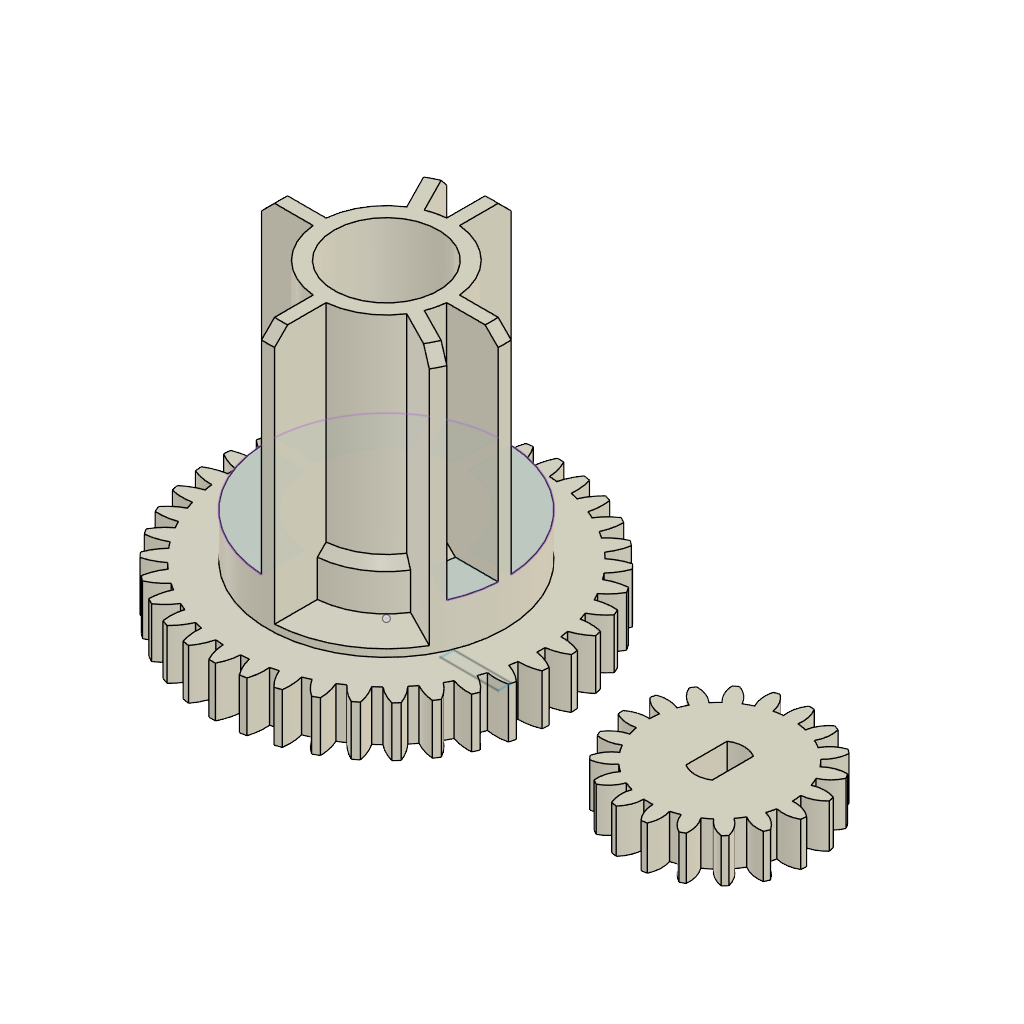
Roue_Store_D27 et pignon (Autodesk Fusion 360 design; units mm, degrees)
Autodesk Fusion 360 part; units mm, degrees
note: some values were not read from the file. Set by a fixed rule: which face or edge a step refers to.
sketch "Esquisse1" plane through (0, 0, 0) normal (0, 0, 1) x (1, 0, 0)
  circle A0 centre (0, 0) radius 17.75
  dimension "d1" = 35.5
  measures "d1" diameter of A0
extrude "Extrusion1" add sketch "Esquisse1" along normal blind 5.75 makes body 1
sketch "Esquisse2" plane through (0, 0, 0) normal (0, 0, 1) x (1, 0, 0)
  circle A0 centre (0, 0) radius 13.6
  dimension "d4" = 27.2
  measures "d4" diameter of A0
extrude "Extrusion2" add sketch "Esquisse2" along normal blind 5.05 from surface at 5.75 bodies 1
sketch "Esquisse3" plane through (0, 0, 0) normal (0, 0, 1) x (1, 0, 0)
  circle A0 centre (0, 0) radius 7.7
  dimension "d8" = 15.4
  measures "d8" diameter of A0
extrude "Extrusion3" add sketch "Esquisse3" along normal blind 24.8 from surface at 10.8 bodies 1
sketch "Esquisse4" plane through (0, 0, 0) normal (0, 0, 1) x (1, 0, 0)
  circle A0 centre (0, 0) radius 11
  dimension "d12" = 22
  measures "d12" diameter of A0
extrude "Extrusion4" cut sketch "Esquisse4" along normal blind 5.5 bodies 1
sketch "Esquisse5" plane through (0, 0, 0) normal (0, 0, 1) x (1, 0, 0)
  circle A0 centre (0, 0) radius 3
  dimension "d15" = 6
  measures "d15" diameter of A0
extrude "Extrusion5" cut sketch "Esquisse5" along normal through all bodies 1
sketch "Esquisse6" plane through (0, 0, 0) normal (0, 0, 1) x (1, 0, 0)
  circle A0 centre (0, 0) radius 6
  dimension "d17" = 12
  measures "d17" diameter of A0
extrude "Extrusion6" cut sketch "Esquisse6" against normal blind 20 from surface at 35.6 bodies 1
chamfer "Chanfrein1" distance 1 angle 45 1 edges at (-7.1789, 2.7844, 10.8) tangent chain off on bodies 1
chamfer "Chanfrein2" distance 1.4 angle 45 1 edges at (-5.594, 2.1697, 15.6) tangent chain off on bodies 1
sketch "Esquisse7" plane through (0, 0, 0) normal (0, 0, 1) x (1, 0, 0)
  arc A0 (0.3802, 19.9957) -> (-0.3768, 19.9957) centre (0.0017, -0.0007) ccw
  arc A1 (1.0258, 17.4199) -> (-1.0222, 17.4199) centre (0.0018, 0) ccw
  arc A2 (1.0258, 17.4199) -> (0.3802, 19.9957) centre (-4.7875, 17.3315) ccw
  arc A3 (-0.3768, 19.9957) -> (-1.0222, 17.4199) centre (4.7912, 17.3321) ccw
  dimension "d23" = 40
  dimension "d24" = 34.9
  dimension "d25" = 5.814
  dimension "d26" = 0.757
  dimension "d27" = 2.048
  constraint coincident A0.start A2.end
  constraint coincident A1.start A2.start
  constraint coincident A0.end A3.start
  constraint coincident A1.end A3.end
  constraint horizontal A0.start A0.end
  constraint horizontal A1.start A1.end
  constraint equal A2 A3
  measures "d23" diameter of A0
  measures "d24" diameter of A1
  measures "d25" radius of A2
  measures "d26" horizontal distance of A0.start A0.end
  measures "d27" horizontal distance of A1.start A1.end
extrude "Extrusion7" add sketch "Esquisse7" along normal blind 5.75 bodies 1
pattern_circular "Réseau C1" count 38 over 360 about axis through (0, 0, 1.75) along (0, 0, 1) of "Extrusion7"
sketch "Esquisse8" plane through (0, 0, 0) normal (0, 0, 1) x (1, 0, 0)
  arc A0 (13.5793, -0.75) -> (13.5793, 0.75) centre (0, 0) ccw
  arc A1 (6.9597, -0.75) -> (6.9597, 0.75) centre (0, 0) ccw
  line L0 (13.5793, 0.75) -> (6.9597, 0.75)
  line L1 (13.5793, -0.75) -> (6.9597, -0.75)
  dimension "d32" = 27.2
  dimension "d33" = 14
  dimension "d34" = 1.5
  dimension "d35" = 0.75
  constraint horizontal L0
  constraint horizontal L1
  measures "d32" diameter of A0
  measures "d33" diameter of A1
  measures "d34" vertical distance of A0.start A0.end
  measures "d35" vertical distance of A0.centre A0.end
extrude "Extrusion8" add sketch "Esquisse8" along normal blind 24.8 from surface at 10.8 bodies 1
pattern_circular "Réseau C2" count 4 over 360 about axis through (0, 0, 1.75) along (0, 0, 1) of "Extrusion8"
pattern_circular "Réseau C3" count 2 over 117 about axis through (0, 0, 1.75) along (0, 0, 1) of "Extrusion8"
pattern_circular "Réseau C4" count 2 over 333 about axis through (0, 0, 1.75) along (0, 0, 1) of "Extrusion8"
extrude "Extrusion9" cut 1 faces at (1.385, -11.8617, 10.8) along direction (0, 0, -1) blind 4.2 on bodies 1 bodies 1
chamfer "Chanfrein3" distance 1.5 angle 45 6 edges at (12.1177, -6.1743, 35.6) (13.6, 0, 35.6) (0, 13.6, 35.6) (-6.1743, 12.1177, 35.6) (-13.6, 0, 35.6) (0, -13.6, 35.6) tangent chain off on bodies 1
sketch "Esquisse9" plane through (0, 0, 10.8) normal (0, 0, 1) x (-1, 0, 0)
  line L0 (-8.0634, 3.2668) -> (-12.4397, 5.4966)
  line L1 (0.75, 13.5793) -> (0.75, 8.6676)
  arc A0 (8.6676, 0.75) -> (0.75, 8.6676) centre (0, 0) ccw
  line L2 (8.6676, 0.75) -> (13.5793, 0.75)
  line L3 (13.5793, -0.75) -> (8.6676, -0.75)
  arc A1 (4.6033, -7.3824) -> (8.6676, -0.75) centre (0, 0) ccw
  line L4 (4.6033, -7.3824) -> (6.8331, -11.7588)
  line L5 (5.4966, -12.4397) -> (3.2668, -8.0634)
  arc A2 (0.75, -8.6676) -> (3.2668, -8.0634) centre (0, 0) ccw
  line L6 (0.75, -8.6676) -> (0.75, -13.5793)
  line L7 (-0.75, -13.5793) -> (-0.75, -8.6676)
  arc A3 (-8.6676, -0.75) -> (-0.75, -8.6676) centre (0, 0) ccw
  line L8 (-8.6676, -0.75) -> (-13.5793, -0.75)
  line L9 (-13.5793, 0.75) -> (-8.6676, 0.75)
  arc A4 (-8.0634, 3.2668) -> (-8.6676, 0.75) centre (0, 0) ccw
  arc A5 (-12.4397, 5.4966) -> (-13.5793, 0.75) centre (0, 0) ccw
  arc A6 (0.75, -13.5793) -> (5.4966, -12.4397) centre (0, 0) ccw
  arc A7 (13.5793, 0.75) -> (0.75, 13.5793) centre (0, 0) ccw
  arc A8 (-13.5793, -0.75) -> (-0.75, -13.5793) centre (0, 0) ccw
  arc A9 (6.8331, -11.7588) -> (13.5793, -0.75) centre (0, 0) ccw
sketch "Esquisse1 (2)" plane through (0, 0, 0) normal (0, 0, 1) x (1, 0, 0) in component "Pignon v1"
  circle A0 centre (0, 0) radius 8.2
  dimension "d1_1" = 16.4
  measures "d1_1" diameter of A0
extrude "Extrusion1'" add sketch "Esquisse1 (2)" along normal blind 5 separate body makes body 2 in component "Pignon v1"
sketch "Esquisse2 (2)" plane through (0, 0, 0) normal (0, 0, 1) x (1, 0, 0) in component "Pignon v1"
  arc A0 (0.3144, 10.5454) -> (-0.3146, 10.5454) centre (-0.0001, 0.0001) ccw
  arc A1 (0.7689, 7.8625) -> (-0.7691, 7.8625) centre (-0.0001, 0) ccw
  arc A2 (0.7689, 7.8625) -> (0.3144, 10.5454) centre (-2.455, 8.6963) ccw
  arc A3 (-0.3146, 10.5454) -> (-0.7691, 7.8625) centre (2.4548, 8.6962) ccw
  dimension "d4_1" = 21.1
  dimension "d5_1" = 15.8
  dimension "d6_1" = 3.33
  dimension "d7_1" = 0.629
  dimension "d8_1" = 1.538
  constraint coincident A0.start A2.end
  constraint coincident A1.start A2.start
  constraint coincident A0.end A3.start
  constraint coincident A1.end A3.end
  constraint horizontal A0.start A0.end
  constraint horizontal A1.start A1.end
  constraint equal A2 A3
  measures "d4_1" diameter of A0
  measures "d5_1" diameter of A1
  measures "d6_1" radius of A2
  measures "d7_1" horizontal distance of A0.start A0.end
  measures "d8_1" horizontal distance of A1.start A1.end
extrude "Extrusion2'" add sketch "Esquisse2 (2)" along normal blind 5 bodies 2 in component "Pignon v1"
pattern_circular "Réseau C1'" count 19 over 360 about axis through (0, 0, 1.75) along (0, 0, 1) of "Extrusion2'" in component "Pignon v1"
sketch "Esquisse3 (2)" plane through (0, 0, 0) normal (0, 0, 1) x (1, 0, 0) in component "Pignon v1"
  arc A0 (1.5, 2.3643) -> (-1.5, 2.3643) centre (0, 0) ccw
  arc A1 (-1.5, -2.3643) -> (1.5, -2.3643) centre (0, 0) ccw
  line L0 (1.5, -2.3643) -> (1.5, 2.3643)
  line L1 (-1.5, 2.3643) -> (-1.5, -2.3643)
  dimension "d13_1" = 5.6
  dimension "d14_1" = 3
  constraint vertical L0
  constraint vertical L1
  constraint horizontal A0.start A0.end
  constraint equal A0 A1
  measures "d13_1" diameter of A0
  measures "d14_1" horizontal distance of A0.start A0.end
extrude "Extrusion3'" cut sketch "Esquisse3 (2)" along normal through all bodies 2 in component "Pignon v1"
component "Pignon v1" placed x (1, 0, 0) y (0, 1, 0) z (0, 0, 1) at (38.2537, 0, 0)
equation "d19 = -( 20 mm )"
named bodies: "Roue_Store", "Pignon"
